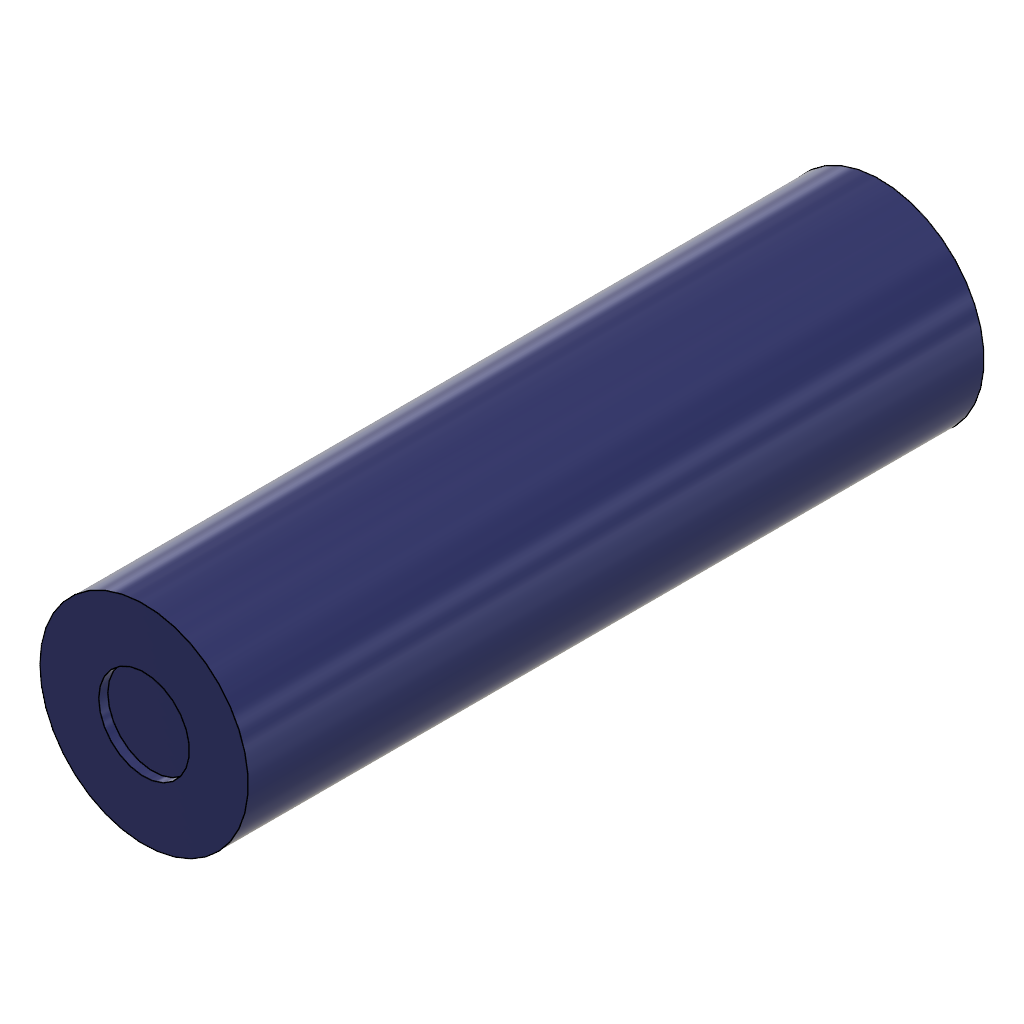
BatteryModule_4S2P (Autodesk Fusion 360 archive; units mm, degrees)
design "battrey"
part number: 2026-11-03-19-33-55-284
Autodesk Fusion 360 part; units mm, degrees
sketch "Sketch1" plane through (0, 0, 0) normal (0, 0, 1) x (1, 0, 0)
  circle A0 centre (0, 0) radius 9.2
  dimension "d1" = 18.4
  constraint coincident A0.centre origin
  measures "d1" diameter of A0
extrude "Extrude1" add sketch "Sketch1" along normal blind 65
sketch "Sketch2" plane through (0, 0, 65) normal (0, 0, 1) x (1, 0, 0)
  circle A0 centre (0, 0) radius 9.2
  circle A1 centre (0, 0) radius 4
  dimension "d4" = 8
  constraint coincident A0.centre A1.centre
  measures "d4" diameter of A1
extrude "Extrude2" cut sketch "Sketch2" against normal blind 0.8 contours A1

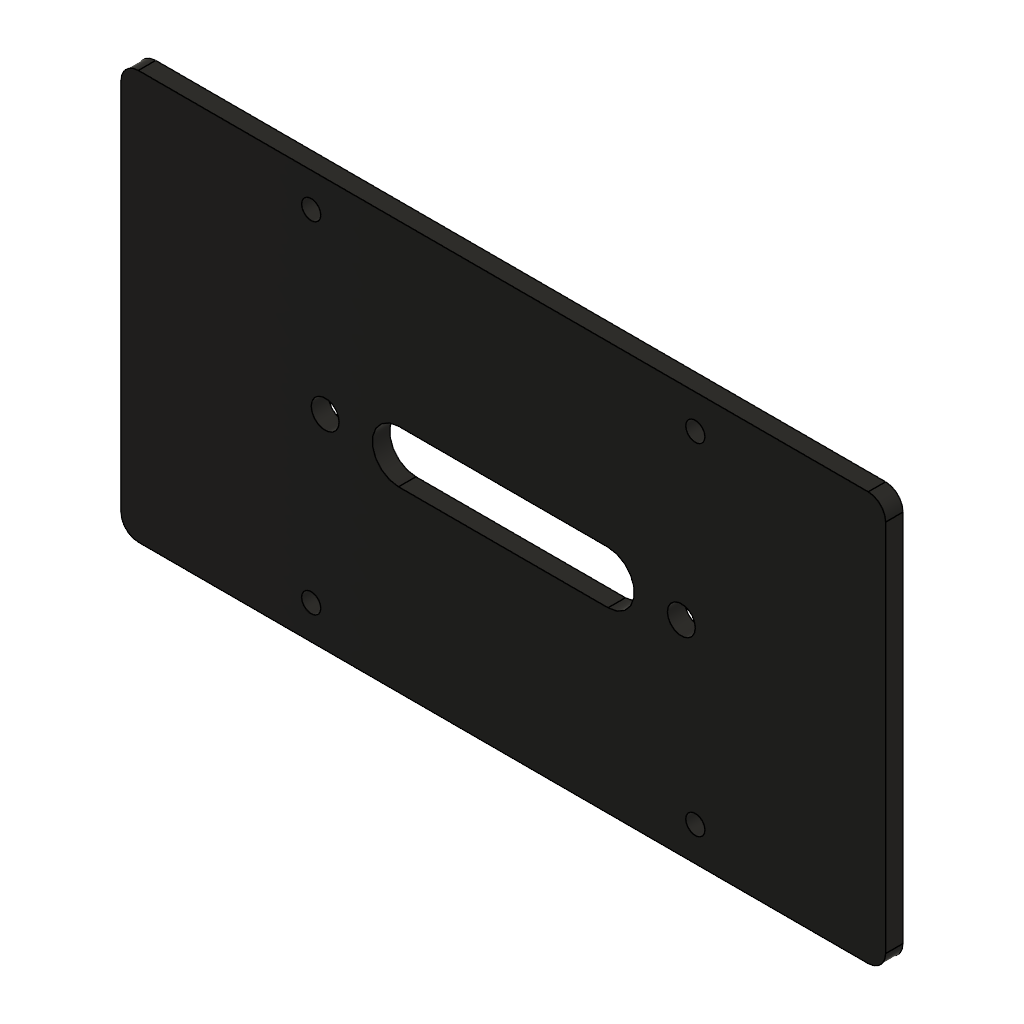
design "BMS_PLATE"
part number: 2026-11-04-20-02-31-986
Autodesk Fusion 360 part; units mm, degrees
sketch "Sketch1" plane through (0, 0, 0) normal (0, 0, 1) x (1, 0, 0)
  line L0 (43.8, -23.4) -> (-43.8, -23.4)
  line L1 (-43.8, -23.4) -> (-43.8, 23.4)
  line L2 (-43.8, 23.4) -> (43.8, 23.4)
  line L3 (43.8, 23.4) -> (43.8, -23.4)
  line L4 (43.8, -23.4) -> (-43.8, 23.4) construction
  line L5 (-43.8, -23.4) -> (43.8, 23.4) construction
  dimension "d1" = 46.8
  dimension "d2" = 87.6
  constraint horizontal L0
  constraint perpendicular L0 L1
  constraint parallel L0 L2
  constraint parallel L1 L3
  constraint coincident L4 origin
  constraint coincident L5 origin
  measures "d1" distance of L0.end L1.end
  measures "d2" distance of L1.end L2.end
extrude "Extrude1" add sketch "Sketch1" along normal blind 2
sketch "Sketch2" plane through (0, 0, 0) normal (0, 0, -1) x (-1, 0, 0)
  line L0 (43.8, 23.4) -> (-43.8, 23.4)
  line L1 (-43.8, 23.4) -> (-43.8, -23.4)
  line L2 (-43.8, -23.4) -> (43.8, -23.4)
  circle A0 centre (22, -19.5) radius 1.1
  circle A1 centre (-22, -19.5) radius 1.1
  circle A2 centre (22, 19.5) radius 1.1
  circle A3 centre (-22, 19.5) radius 1.1
  circle A4 centre (20.4, 0) radius 1.6
  circle A5 centre (-20.4, 0) radius 1.6
  line L3 (12, 3) -> (-12, 3)
  arc A6 (-12, 3) -> (-12, -3) centre (-12, 0) ccw
  line L4 (-12, -3) -> (12, -3)
  arc A7 (12, -3) -> (12, 3) centre (12, 0) ccw
  line L5 (12, 0) -> (-12, 0) construction
  line L6 (43.8, -23.4) -> (43.8, 23.4)
  dimension "d5" = 2.2
  dimension "d7" = 3.9
  dimension "d8" = 2.2
  dimension "d10" = 3.9
  dimension "d11" = 2.2
  dimension "d13" = 42.9
  dimension "d14" = 2.2
  dimension "d16" = 42.9
  dimension "d17" = 3.2
  dimension "d19" = 23.4
  dimension "d20" = 3.2
  dimension "d22" = 23.4
  dimension "d30" = 24
  dimension "d31" = 6
  dimension "d32" = 31.8
  dimension "d33" = 23.4
  constraint tangent L3 A6
  constraint tangent A6 L4
  constraint parallel L3 L4
  constraint tangent L4 A7
  constraint tangent L3 A7
  constraint horizontal L5
  measures "d5" diameter of A0
  measures "d7" distance of L2 A0.centre
  measures "d8" diameter of A1
  measures "d10" distance of L2 A1.centre
  measures "d11" diameter of A2
  measures "d13" distance of L2 A2.centre
  measures "d14" diameter of A3
  measures "d16" distance of L2 A3.centre
  measures "d17" diameter of A4
  measures "d19" distance of L2 A4.centre
  measures "d20" diameter of A5
  measures "d22" distance of L2 A5.centre
  measures "d30" distance of A7.centre A6.centre
  measures "d31" diameter of A6
  measures "d32" distance of A7.centre L6
  measures "d33" distance of L2 L5
extrude "Extrude2" cut sketch "Sketch2" against normal through all contours A0 | A1 | A2 | A3 | A4 | A5 | L3 A6 L4 A7
fillet "Fillet1" radius 2 4 edges at (-43.8, -23.4, 1) (43.8, -23.4, 1) (-43.8, 23.4, 1) (43.8, 23.4, 1)

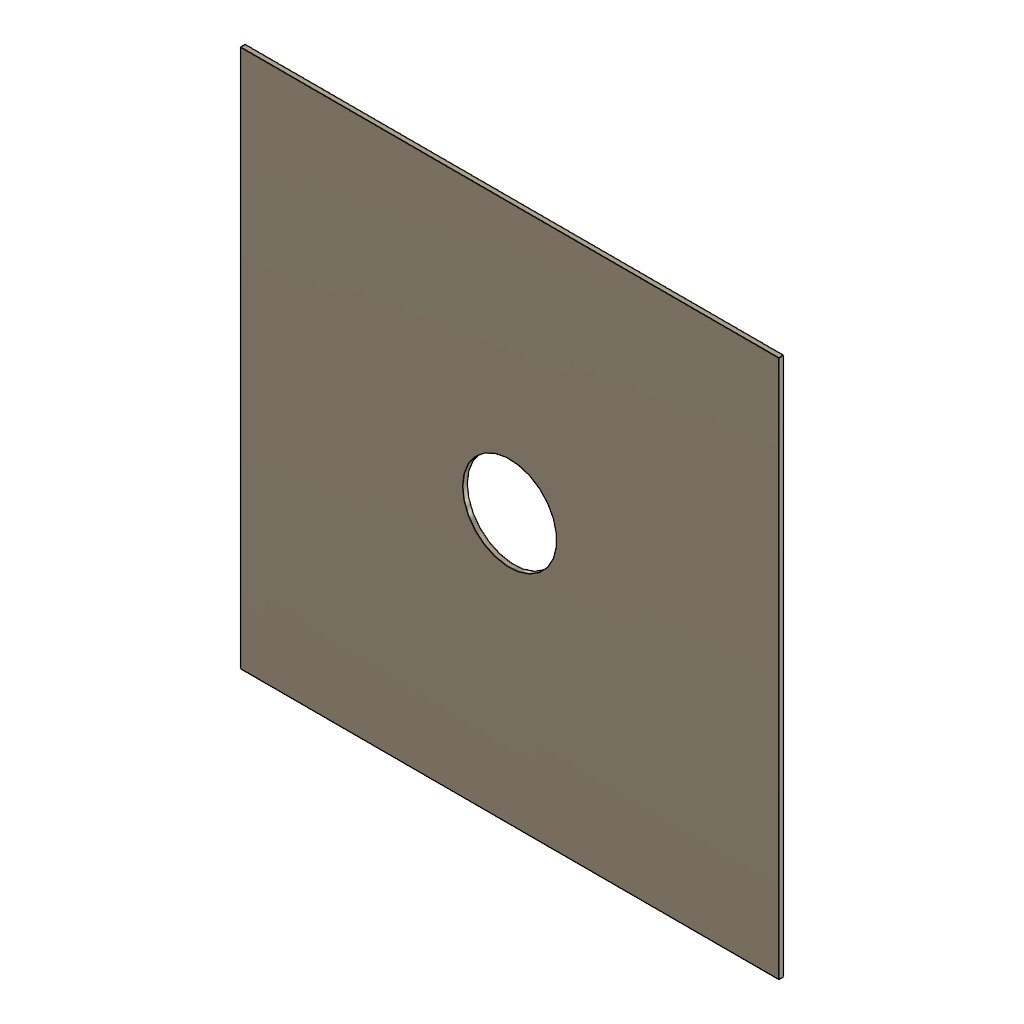
design "STRIP_2X2"
part number: 2026-11-03-20-35-49-898
Autodesk Fusion 360 part; units mm, degrees
sketch "Sketch1" plane through (0, 0, 0) normal (0, 0, 1) x (1, 0, 0)
  line L0 (17.2, 17.2) -> (-17.2, 17.2)
  line L1 (-17.2, 17.2) -> (-17.2, -17.2)
  line L2 (-17.2, -17.2) -> (17.2, -17.2)
  line L3 (17.2, -17.2) -> (17.2, 17.2)
  line L4 (17.2, 17.2) -> (-17.2, -17.2) construction
  line L5 (-17.2, 17.2) -> (17.2, -17.2) construction
  circle A0 centre (0, 0) radius 3
  dimension "d1" = 34.4
  dimension "d2" = 34.4
  dimension "d3" = 6
  constraint horizontal L0
  constraint perpendicular L0 L1
  constraint parallel L0 L2
  constraint parallel L1 L3
  constraint coincident L4 A0.centre
  constraint coincident L5 A0.centre
  constraint coincident A0.centre origin
  measures "d1" distance of L0.end L1.end
  measures "d2" distance of L1.end L2.end
  measures "d3" diameter of A0
extrude "Extrude1" add sketch "Sketch1" along normal blind 0.3

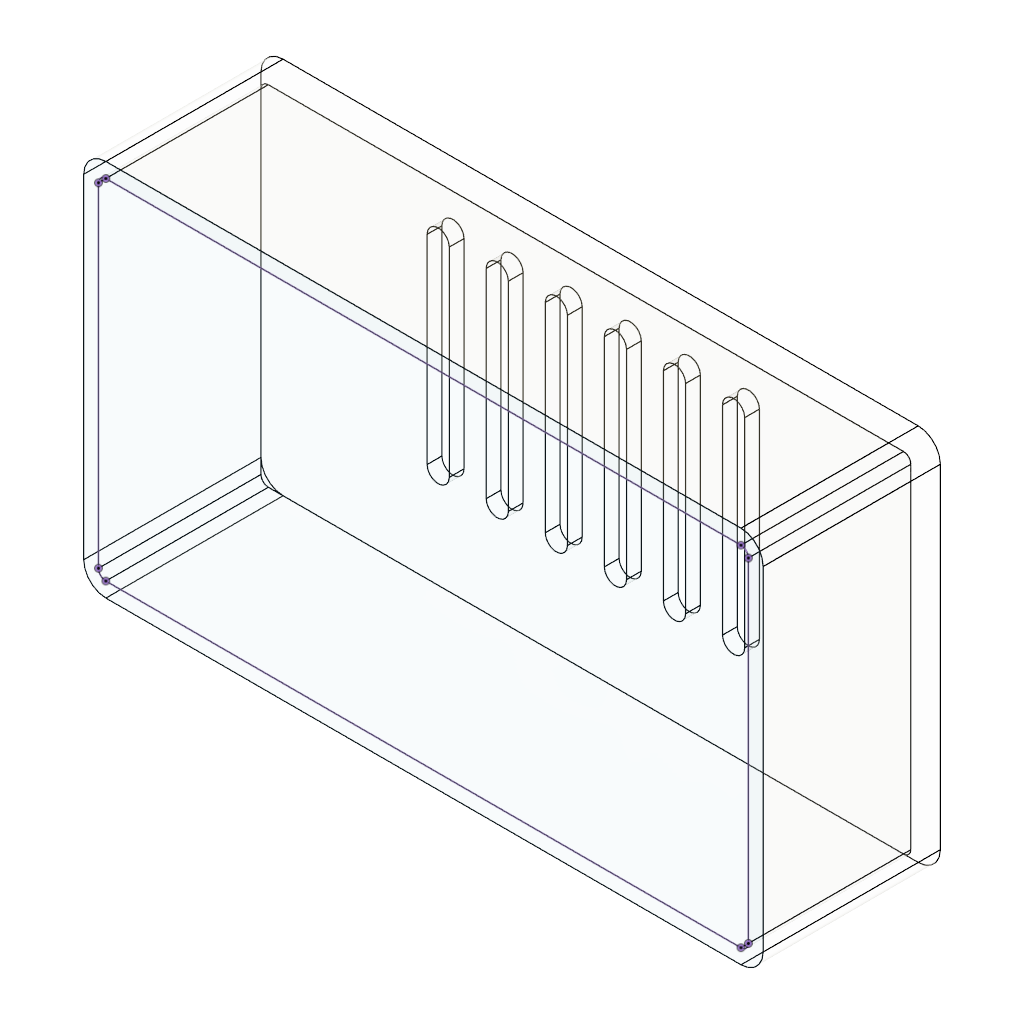
design "Vented lid"
part number: 2026-11-05-20-38-33-133
Autodesk Fusion 360 part; units mm, degrees
sketch "Sketch1" plane through (0, 0, 0) normal (0, 0, 1) x (1, 0, 0)
  line L0 (46, -25.6) -> (-46, -25.6)
  line L1 (-46, -25.6) -> (-46, 25.6)
  line L2 (-46, 25.6) -> (46, 25.6)
  line L3 (46, 25.6) -> (46, -25.6)
  line L4 (46, -25.6) -> (-46, 25.6) construction
  line L5 (-46, -25.6) -> (46, 25.6) construction
  dimension "d1" = 92
  dimension "d2" = 51.2
  constraint horizontal L0
  constraint perpendicular L0 L1
  constraint parallel L0 L2
  constraint parallel L1 L3
  constraint coincident L4 origin
  constraint coincident L5 origin
  measures "d1" distance of L0.start L0.end
  measures "d2" distance of L0.end L1.end
extrude "Extrude1" add sketch "Sketch1" along normal blind 24
fillet "Fillet1" radius 3 4 edges at (-46, 25.6, 12) (46, 25.6, 12) (-46, -25.6, 12) (46, -25.6, 12)
shell "Shell1" thickness 2 removed faces 1 at (-14.3333, 8.5333, 24)
sketch "Sketch2" plane through (0, 0, 24) normal (0, 0, 1) x (1, 0, 0)
  arc A0 (43, -25.6) -> (46, -22.6) centre (43, -22.6) ccw
  line L0 (46, -22.6) -> (46, 22.6)
  arc A1 (46, 22.6) -> (43, 25.6) centre (43, 22.6) ccw
  line L1 (43, 25.6) -> (-43, 25.6)
  arc A2 (-43, 25.6) -> (-46, 22.6) centre (-43, 22.6) ccw
  line L2 (-46, 22.6) -> (-46, -22.6)
  arc A3 (-46, -22.6) -> (-43, -25.6) centre (-43, -22.6) ccw
  line L3 (-43, -25.6) -> (43, -25.6)
  line L4 (-21.5, 16.812) -> (-21.5, -10.188)
  arc A4 (-21.5, -10.188) -> (-18.5, -10.188) centre (-20, -10.188) ccw
  line L5 (-18.5, -10.188) -> (-18.5, 16.812)
  arc A5 (-18.5, 16.812) -> (-21.5, 16.812) centre (-20, 16.812) ccw
  line L6 (-20, 16.812) -> (-20, -10.188) construction
  line L7 (-13.5, 16.812) -> (-13.5, -10.188)
  line L8 (-12, 16.812) -> (-12, -10.188) construction
  arc A6 (-13.5, -10.188) -> (-10.5, -10.188) centre (-12, -10.188) ccw
  line L9 (-10.5, -10.188) -> (-10.5, 16.812)
  arc A7 (-10.5, 16.812) -> (-13.5, 16.812) centre (-12, 16.812) ccw
  line L10 (-5.5, 16.812) -> (-5.5, -10.188)
  line L11 (-4, 16.812) -> (-4, -10.188) construction
  arc A8 (-5.5, -10.188) -> (-2.5, -10.188) centre (-4, -10.188) ccw
  line L12 (-2.5, -10.188) -> (-2.5, 16.812)
  arc A9 (-2.5, 16.812) -> (-5.5, 16.812) centre (-4, 16.812) ccw
  line L13 (2.5, 16.812) -> (2.5, -10.188)
  line L14 (4, 16.812) -> (4, -10.188) construction
  arc A10 (2.5, -10.188) -> (5.5, -10.188) centre (4, -10.188) ccw
  line L15 (5.5, -10.188) -> (5.5, 16.812)
  arc A11 (5.5, 16.812) -> (2.5, 16.812) centre (4, 16.812) ccw
  line L16 (10.5, 16.812) -> (10.5, -10.188)
  line L17 (12, 16.812) -> (12, -10.188) construction
  arc A12 (10.5, -10.188) -> (13.5, -10.188) centre (12, -10.188) ccw
  line L18 (13.5, -10.188) -> (13.5, 16.812)
  arc A13 (13.5, 16.812) -> (10.5, 16.812) centre (12, 16.812) ccw
  line L19 (18.5, 16.812) -> (18.5, -10.188)
  line L20 (20, 16.812) -> (20, -10.188) construction
  arc A14 (18.5, -10.188) -> (21.5, -10.188) centre (20, -10.188) ccw
  line L21 (21.5, -10.188) -> (21.5, 16.812)
  arc A15 (21.5, 16.812) -> (18.5, 16.812) centre (20, 16.812) ccw
  arc A16 (44, 22.6) -> (43, 23.6) centre (43, 22.6) ccw
  line L22 (44, 22.6) -> (44, -22.6)
  arc A17 (43, -23.6) -> (44, -22.6) centre (43, -22.6) ccw
  line L23 (43, -23.6) -> (-43, -23.6)
  arc A18 (-44, -22.6) -> (-43, -23.6) centre (-43, -22.6) ccw
  line L24 (-44, -22.6) -> (-44, 22.6)
  arc A19 (-43, 23.6) -> (-44, 22.6) centre (-43, 22.6) ccw
  line L25 (-43, 23.6) -> (43, 23.6)
  dimension "d8" = 27
  dimension "d9" = 3
  dimension "d11" = 18.5
  dimension "d14" = 8
  dimension "d15" = 0
  constraint tangent L4 A4
  constraint tangent A4 L5
  constraint parallel L4 L5
  constraint tangent L5 A5
  constraint tangent L4 A5
  constraint perpendicular L3 L6
  measures "d8" distance of A5.centre A4.centre
  measures "d9" diameter of A4
  measures "d11" distance of origin L5
extrude "Extrude2" cut sketch "Sketch2" against normal through all contours L4 A4 L5 A5 | L7 A6 L9 A7 | L10 A8 L12 A9 | L13 A10 L15 A11 | L16 A12 L18 A13 | L19 A14 L21 A15
sketch "Sketch3" plane through (0, 0, 24) normal (0, 0, 1) x (1, 0, 0)
  arc A0 (43, -25.6) -> (46, -22.6) centre (43, -22.6) ccw
  line L0 (46, -22.6) -> (46, 22.6)
  arc A1 (46, 22.6) -> (43, 25.6) centre (43, 22.6) ccw
  line L1 (43, 25.6) -> (-43, 25.6)
  arc A2 (-43, 25.6) -> (-46, 22.6) centre (-43, 22.6) ccw
  line L2 (-46, 22.6) -> (-46, -22.6)
  arc A3 (-46, -22.6) -> (-43, -25.6) centre (-43, -22.6) ccw
  line L3 (-43, -25.6) -> (43, -25.6)
  arc A4 (44, 22.6) -> (43, 23.6) centre (43, 22.6) ccw
  line L4 (44, 22.6) -> (44, -22.6)
  arc A5 (43, -23.6) -> (44, -22.6) centre (43, -22.6) ccw
  line L5 (43, -23.6) -> (-43, -23.6)
  arc A6 (-44, -22.6) -> (-43, -23.6) centre (-43, -22.6) ccw
  line L6 (-44, -22.6) -> (-44, 22.6)
  arc A7 (-43, 23.6) -> (-44, 22.6) centre (-43, 22.6) ccw
  line L7 (-43, 23.6) -> (43, 23.6)

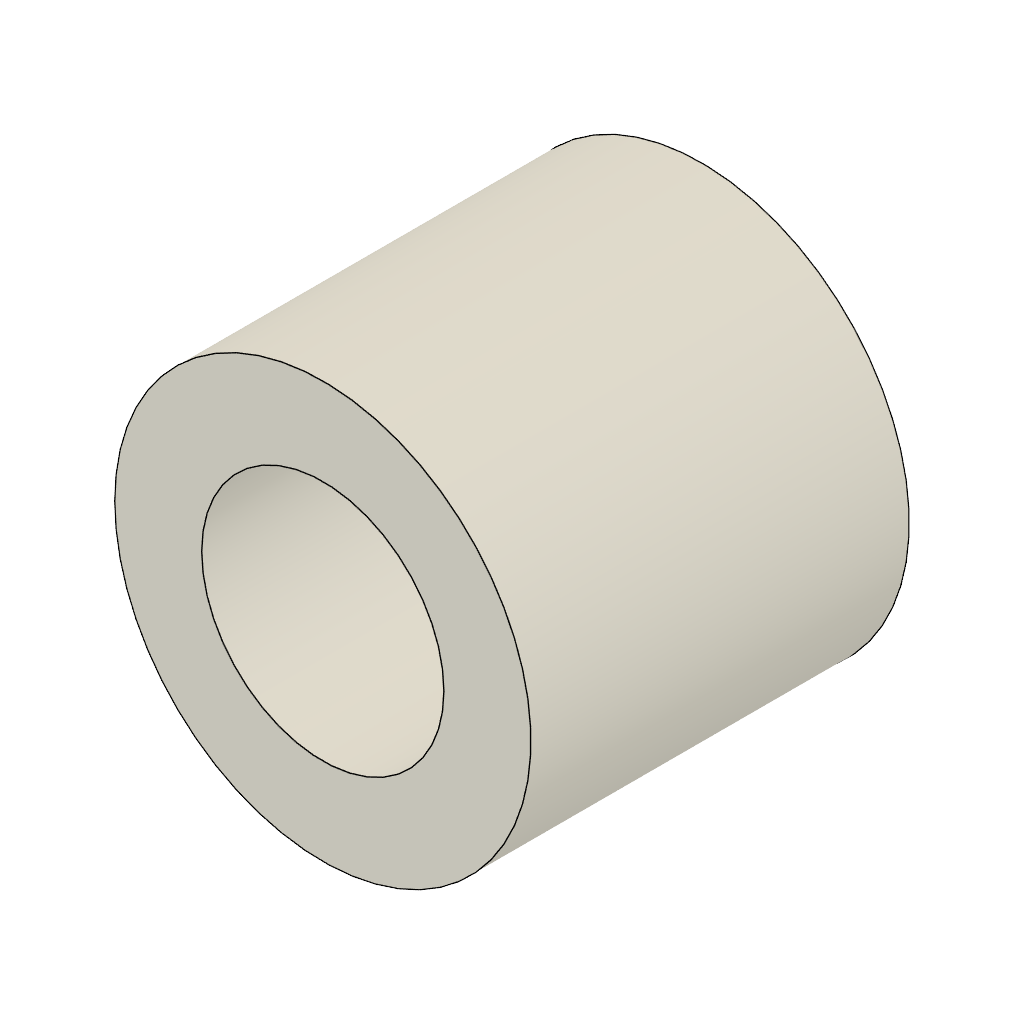
design "spacer"
part number: 2026-11-05-19-42-56-678
Autodesk Fusion 360 part; units mm, degrees
sketch "Sketch1" plane through (0, 0, 0) normal (0, 0, 1) x (1, 0, 0)
  circle A0 centre (0, 0) radius 1.6
  circle A1 centre (0, 0) radius 2.75
  dimension "d1" = 3.2
  dimension "d2" = 5.5
  constraint coincident A0.centre A1.centre
  constraint concentric A0 A1
  measures "d1" diameter of A0
  measures "d2" diameter of A1
extrude "Extrude1" add sketch "Sketch1" along normal blind 5

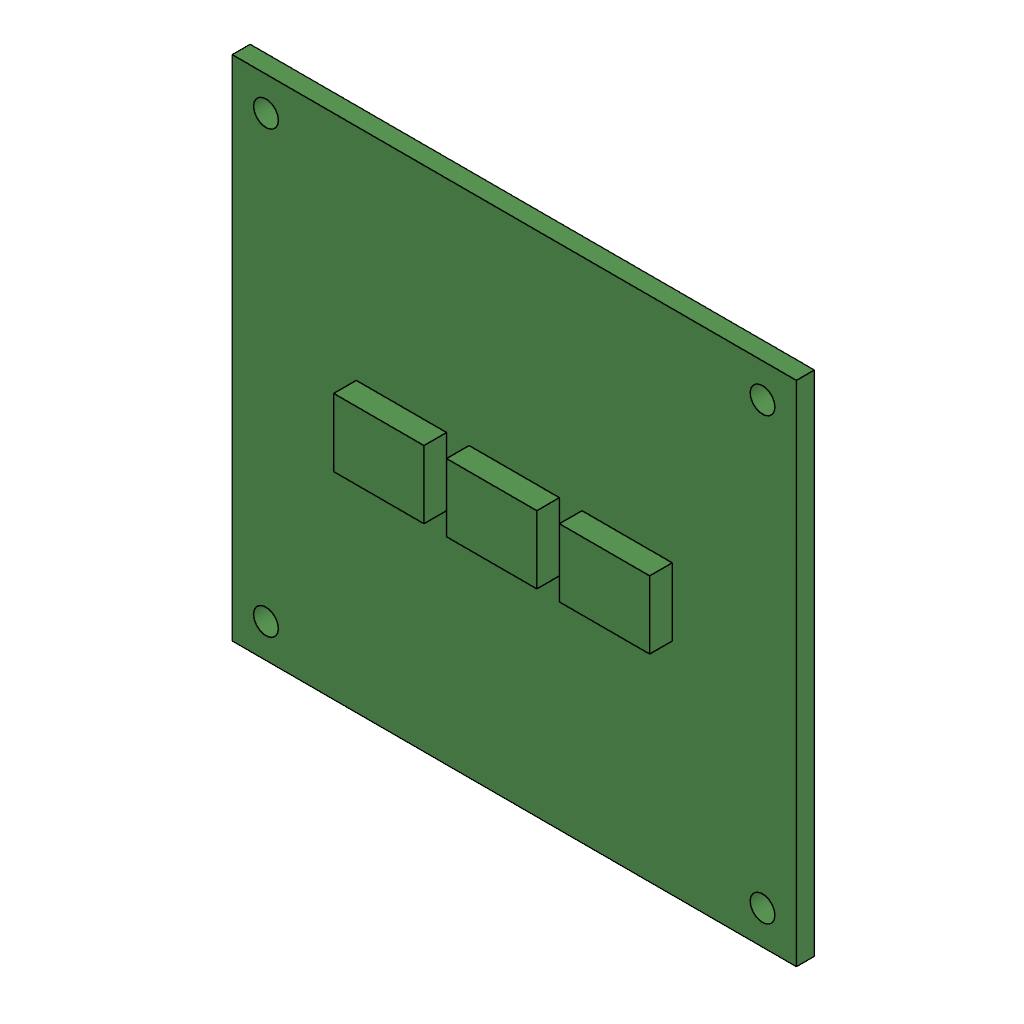
design "Dummy BMS board"
part number: 2026-11-05-19-52-12-505
Autodesk Fusion 360 part; units mm, degrees
sketch "Sketch1" plane through (0, 0, 0) normal (0, 0, 1) x (1, 0, 0)
  line L0 (25, -22.5) -> (-25, -22.5)
  line L1 (-25, -22.5) -> (-25, 22.5)
  line L2 (-25, 22.5) -> (25, 22.5)
  line L3 (25, 22.5) -> (25, -22.5)
  line L4 (25, -22.5) -> (-25, 22.5) construction
  line L5 (-25, -22.5) -> (25, 22.5) construction
  circle A0 centre (-22, 19.5) radius 1.1
  circle A1 centre (22, 19.5) radius 1.1
  circle A2 centre (-22, -19.5) radius 1.1
  circle A3 centre (22, -19.5) radius 1.1
  dimension "d1" = 50
  dimension "d2" = 45
  dimension "d3" = 2.2
  dimension "d4" = 3
  dimension "d5" = 3
  dimension "d6" = 2.2
  dimension "d7" = 3
  dimension "d8" = 47
  dimension "d9" = 2.2
  dimension "d10" = 3
  dimension "d11" = 42
  dimension "d12" = 2.2
  dimension "d13" = 47
  dimension "d14" = 42
  constraint horizontal L0
  constraint perpendicular L0 L1
  constraint parallel L0 L2
  constraint parallel L1 L3
  constraint coincident L4 origin
  constraint coincident L5 origin
  measures "d1" distance of L0.start L0.end
  measures "d2" distance of L0.end L1.end
  measures "d3" diameter of A0
  measures "d4" distance of L1 A0.centre
  measures "d5" distance of L2 A0.centre
  measures "d6" diameter of A1
  measures "d7" distance of L2 A1.centre
  measures "d8" distance of L1 A1.centre
  measures "d9" diameter of A2
  measures "d10" distance of L1 A2.centre
  measures "d11" distance of L2 A2.centre
  measures "d12" diameter of A3
  measures "d13" distance of L1 A3.centre
  measures "d14" distance of L2 A3.centre
extrude "Extrude1" add sketch "Sketch1" along normal blind 1.6
sketch "Sketch2" plane through (0, 0, 1.6) normal (0, 0, 1) x (1, 0, 0)
  circle A0 centre (22, -19.5) radius 1.1
  circle A1 centre (-22, 19.5) radius 1.1
  circle A2 centre (-22, -19.5) radius 1.1
  circle A3 centre (22, 19.5) radius 1.1
  line L0 (25, 22.5) -> (-25, 22.5)
  line L1 (-25, 22.5) -> (-25, -22.5)
  line L2 (-25, -22.5) -> (25, -22.5)
  line L3 (25, -22.5) -> (25, 22.5)
  line L4 (-14, 3) -> (-6, 3)
  line L5 (-6, 3) -> (-6, -3)
  line L6 (-6, -3) -> (-14, -3)
  line L7 (-14, -3) -> (-14, 3)
  line L8 (-4, 3) -> (4, 3)
  line L9 (4, 3) -> (4, -3)
  line L10 (4, -3) -> (-4, -3)
  line L11 (-4, -3) -> (-4, 3)
  line L12 (6, 3) -> (14, 3)
  line L13 (14, 3) -> (14, -3)
  line L14 (14, -3) -> (6, -3)
  line L15 (6, -3) -> (6, 3)
  dimension "d17" = 8
  dimension "d18" = 6
  dimension "d19" = 19.5
  dimension "d20" = 11
  dimension "d21" = 8
  dimension "d22" = 6
  dimension "d23" = 19.5
  dimension "d24" = 21
  dimension "d25" = 8
  dimension "d26" = 6
  dimension "d27" = 19.5
  dimension "d28" = 31
  constraint horizontal L4
  constraint vertical L5
  constraint horizontal L6
  constraint vertical L7
  constraint horizontal L8
  constraint vertical L9
  constraint horizontal L10
  constraint vertical L11
  constraint horizontal L12
  constraint vertical L13
  constraint horizontal L14
  constraint vertical L15
  measures "d17" distance of L4.start L4.end
  measures "d18" distance of L4.end L5.end
  measures "d19" distance of L0 L4
  measures "d20" distance of L1 L7
  measures "d21" distance of L8.start L8.end
  measures "d22" distance of L8.start L10.end
  measures "d23" distance of L0 L8
  measures "d24" distance of L1 L11
  measures "d25" distance of L12.start L12.end
  measures "d26" distance of L12.start L14.end
  measures "d27" distance of L0 L12
  measures "d28" distance of L1 L15
extrude "Extrude2" add sketch "Sketch2" along normal blind 2 contours L4 L5 L6 L7 | L8 L9 L10 L11 | L12 L13 L14 L15

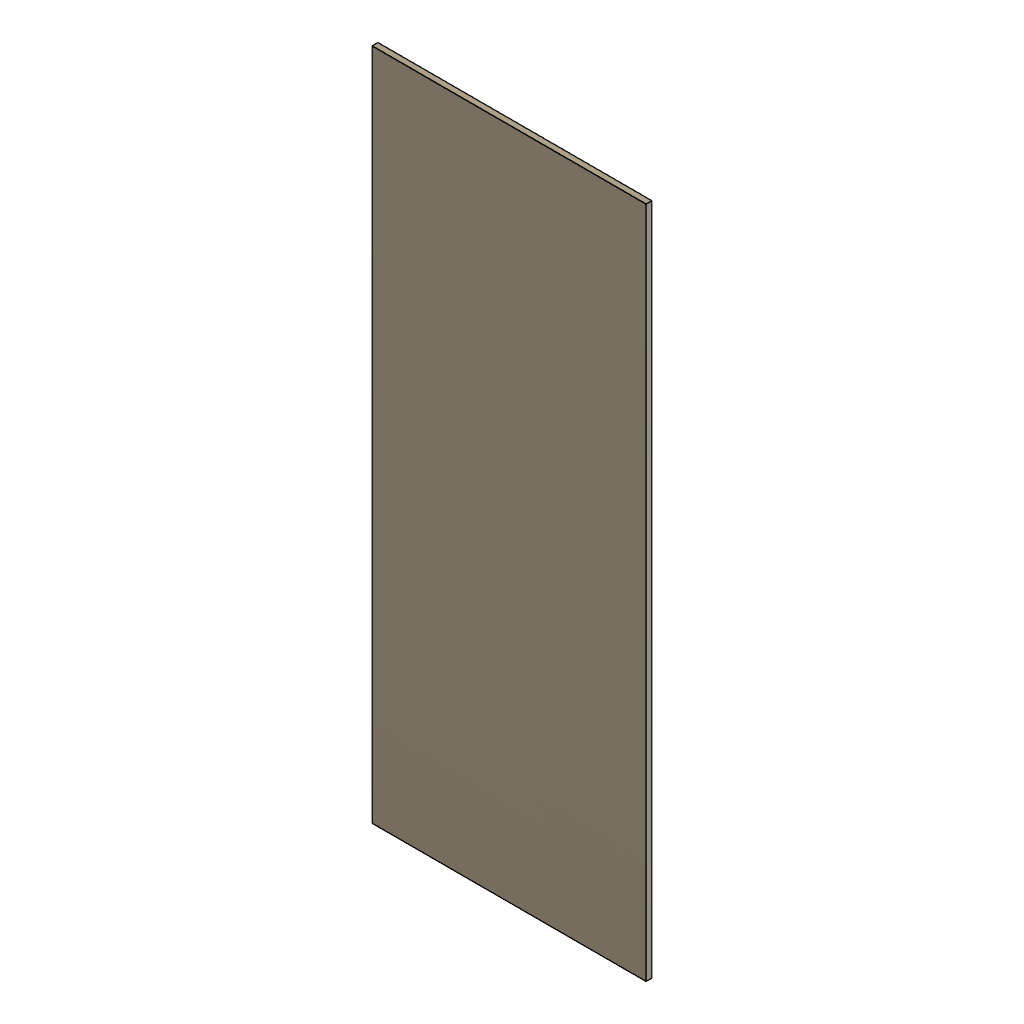
design "strip 1x2"
part number: 2026-11-04-17-59-15-230
Autodesk Fusion 360 part; units mm, degrees
sketch "Sketch1" plane through (0, 0, 0) normal (0, 0, 1) x (1, 0, 0)
  line L0 (0, 0) -> (0, 34.4)
  line L1 (0, 34.4) -> (14, 34.4)
  line L2 (14, 34.4) -> (14, 0)
  line L3 (14, 0) -> (0, 0)
  dimension "d1" = 34.4
  dimension "d2" = 14
  constraint coincident L0.start L3.end
  constraint vertical L0
  constraint perpendicular L0 L1
  constraint perpendicular L1 L2
  constraint equal L0 L2
  measures "d1" distance of L0.start L0.end
  measures "d2" distance of L0.end L1.end
extrude "Extrude1" add sketch "Sketch1" along normal blind 0.3

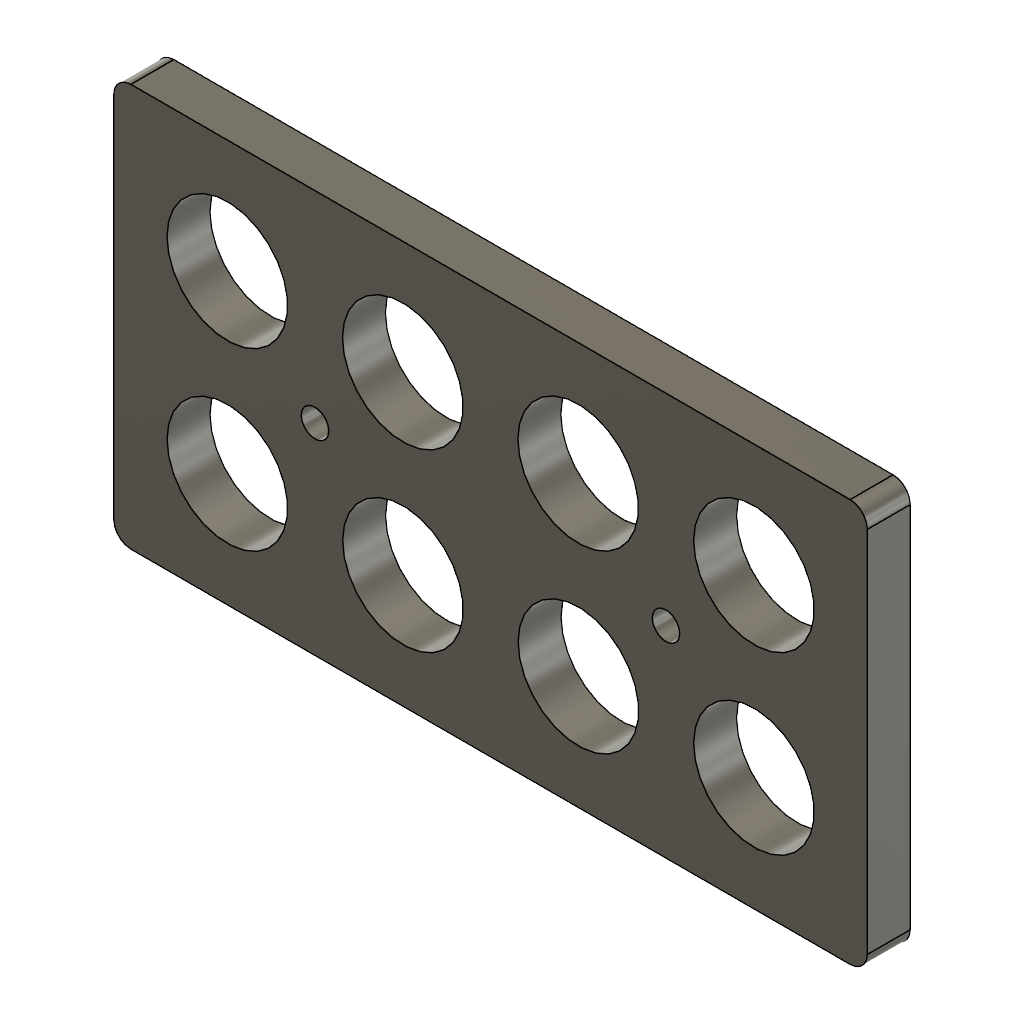
design "cell_HOLDER"
part number: 2026-11-03-18-21-09-550
Autodesk Fusion 360 part; units mm, degrees
sketch "Sketch1" plane through (0, 0, 0) normal (0, 0, 1) x (1, 0, 0)
  line L0 (0, 0) -> (0, 46.8)
  line L1 (0, 0) -> (87.6, 0)
  line L2 (87.6, 0) -> (87.6, 46.8)
  line L3 (0, 46.8) -> (87.6, 46.8)
  circle A0 centre (13.2, 33.6) radius 9.4 construction
  circle A1 centre (13.2, 33.6) radius 9.4
  circle A2 centre (33.6, 33.6) radius 9.4
  circle A3 centre (54, 33.6) radius 9.4
  circle A4 centre (74.4, 33.6) radius 9.4
  circle A5 centre (13.2, 13.2) radius 9.4
  circle A6 centre (33.6, 13.2) radius 9.4
  circle A7 centre (54, 13.2) radius 9.4
  circle A8 centre (74.4, 13.2) radius 9.4
  circle A9 centre (13.2, 33.6) radius 7
  circle A10 centre (13.205, 13.2004) radius 7
  circle A11 centre (33.5969, 33.6052) radius 7
  circle A12 centre (53.9846, 33.6052) radius 7
  circle A13 centre (74.4141, 33.6016) radius 7
  circle A14 centre (13.2, 33.6) radius 7
  circle A15 centre (33.6146, 13.2004) radius 7
  circle A16 centre (54.0125, 13.2004) radius 7
  circle A17 centre (74.4157, 13.2066) radius 7
  point P0 (13.205, 13.2004)
  dimension "d1" = 46.8
  dimension "d2" = 87.6
  dimension "d8" = 18.8
  dimension "d9" = 13.2
  dimension "d10" = 13.2
  dimension "d11" = 20.4
  dimension "d14" = 14
  dimension "d15" = 14
  dimension "d16" = 14
  dimension "d17" = 14
  dimension "d18" = 14
  dimension "d19" = 14
  dimension "d20" = 14
  dimension "d21" = 14
  dimension "d22" = 14
  constraint coincident L0.start L1.start
  constraint vertical L0
  constraint perpendicular L0 L1
  constraint perpendicular L1 L2
  constraint equal L1 L3
  constraint equal L0 L2
  constraint equal A1 A2
  constraint equal A2 A3
  constraint equal A3 A4
  constraint equal A7 A8
  constraint equal A6 A7
  constraint equal A5 A6
  constraint equal A0 A5
  constraint concentric A1 A9
  measures "d1" distance of L0.start L0.end
  measures "d2" distance of L0.start L1.end
  measures "d8" diameter of A1
  measures "d9" distance of L0 A5.centre
  measures "d10" distance of L3 A0.centre
  measures "d11" distance of A2.centre A3.centre
  measures "d14" diameter of A9
  measures "d15" diameter of A10
  measures "d16" diameter of A11
  measures "d17" diameter of A12
  measures "d18" diameter of A13
  measures "d19" diameter of A14
  measures "d20" diameter of A15
  measures "d21" diameter of A16
  measures "d22" diameter of A17
extrude "Extrude1" add sketch "Sketch1" along normal blind 5 contours L0 L1 L2 L3 | A1 | A2 | A3 | A4 | A5 | A6 | A7 | A8
fillet "Fillet1" radius 2 4 edges at (0, 46.8, 2.5) (87.6, 46.8, 2.5) (0, 0, 2.5) (87.6, 0, 2.5)
sketch "Sketch2" plane through (0, 0, 0) normal (0, 0, -1) x (-1, 0, 0)
  arc A0 (-87.6, 2) -> (-85.6, 0) centre (-85.6, 2) ccw
  line L0 (-85.6, 0) -> (-2, 0)
  arc A1 (-2, 0) -> (0, 2) centre (-2, 2) ccw
  line L1 (0, 2) -> (0, 44.8)
  arc A2 (0, 44.8) -> (-2, 46.8) centre (-2, 44.8) ccw
  line L2 (-2, 46.8) -> (-85.6, 46.8)
  arc A3 (-85.6, 46.8) -> (-87.6, 44.8) centre (-85.6, 44.8) ccw
  line L3 (-87.6, 44.8) -> (-87.6, 2)
  circle A4 centre (-54.0125, 13.2004) radius 7
  circle A5 centre (-33.6146, 13.2004) radius 7
  circle A6 centre (-33.5969, 33.6052) radius 7
  circle A7 centre (-74.4157, 13.2066) radius 7
  circle A8 centre (-74.4141, 33.6016) radius 7
  circle A9 centre (-13.205, 13.2004) radius 7
  circle A10 centre (-53.9846, 33.6052) radius 7
  circle A11 centre (-13.2, 33.6) radius 7
  circle A12 centre (-23.4, 23.4) radius 1.6
  circle A13 centre (-64.2, 23.4) radius 1.6
  point P0 (-64.2, 23.4)
  dimension "d27" = 3.2
  dimension "d28" = 3.2
  constraint coincident P0 A13.centre
  measures "d27" diameter of A12
  measures "d28" diameter of A13
extrude "Extrude2" cut sketch "Sketch2" against normal blind 14 contours A12 | A13
